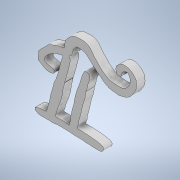
# Autodesk Inventor part: PI
Saved by Autodesk Inventor 2022.6 (Build 266554000, 554)
## iProperties
Created: 2024-11-29
Part Number: PI
Material: Generic
Document SubType Name: Modeling
Designer: Dragos Macovei
Density: 1 g/cm^3
Appearance: Default
Author: Dragos Macovei
Autodesk Inventor part; units mm, degrees
ref_plane "YZ Plane" through (0, 0, 0) normal (1, 0, 0) x (0, 1, 0)
ref_plane "XZ Plane" through (0, 0, 0) normal (0, 1, 0) x (-1, 0, 0)
ref_plane "XY Plane" through (0, 0, 0) normal (0, 0, 1) x (1, 0, 0)
sketch "Sketch1" plane through (0, 0, 0) normal (0, 0, 1) x (1, 0, 0)
  line L0 (0, 0) -> (-40, 0)
  line L1 (-40, 0) -> (-40, 40)
  line L2 (-40, 40) -> (0, 40)
  line L3 (0, 40) -> (0, 0)
  line L4 (-38.5113, 5.4605) -> (-38.1213, 5.6556) construction
  line L5 (-38.1213, 5.6556) -> (-37.6228, 5.8723) construction
  line L6 (-37.6228, 5.8723) -> (-37.2327, 5.8723) construction
  line L7 (-37.2327, 5.8723) -> (-36.6476, 6.089) construction
  line L8 (-36.6476, 6.089) -> (-35.8891, 6.089) construction
  line L9 (-35.8891, 6.089) -> (-34.4588, 6.089) construction
  line L10 (-34.4588, 6.089) -> (-34.4588, 6.6308) construction
  line L11 (-34.4588, 6.6308) -> (-34.1771, 7.3243) construction
  line L12 (-34.1771, 7.3243) -> (-34.0037, 8.1478) construction
  line L13 (-34.0037, 8.1478) -> (-33.7003, 9.058) construction
  line L14 (-33.7003, 9.058) -> (-33.3969, 10.2499) construction
  line L15 (-33.3969, 10.2499) -> (-33.2452, 11.0301) construction
  line L16 (-33.2452, 11.0301) -> (-33.2452, 11.6802) construction
  line L17 (-33.2452, 11.6802) -> (-32.9635, 12.2653) construction
  line L18 (-32.9635, 12.2653) -> (-32.7901, 13.0672) construction
  line L19 (-32.7901, 13.0672) -> (-32.5084, 13.804) construction
  line L20 (-32.5084, 13.804) -> (-32.27, 14.6492) construction
  line L21 (-32.27, 14.6492) -> (-32.075, 15.4293) construction
  line L22 (-32.075, 15.4293) -> (-31.9449, 16.1011) construction
  line L23 (-31.9449, 16.1011) -> (-31.7066, 16.6863) construction
  line L24 (-31.7066, 16.6863) -> (-31.4682, 17.2064) construction
  line L25 (-31.4682, 17.2064) -> (-31.3381, 17.2064) construction
  line L26 (-31.3381, 17.2064) -> (-30.9914, 18.42) construction
  line L27 (-30.9914, 18.42) -> (-30.623, 19.3518) construction
  line L28 (-30.623, 19.3518) -> (-30.2979, 20.2187) construction
  line L29 (-30.2979, 20.2187) -> (-30.1246, 21.3456) construction
  line L30 (-30.1246, 21.3456) -> (-29.7995, 22.3208) construction
  line L31 (-29.7995, 22.3208) -> (-29.6695, 23.2527) construction
  line L32 (-29.6695, 23.2527) -> (-29.4094, 24.0112) construction
  line L33 (-29.4094, 24.0112) -> (-29.171, 24.7913) construction
  line L34 (-29.171, 24.7913) -> (-29.0029, 25.0509) construction
  line L35 (-29.0029, 25.0509) -> (-28.9426, 25.4128) construction
  line L36 (-28.9426, 25.4128) -> (-28.8159, 25.7143) construction
  line L37 (-28.8159, 25.7143) -> (-28.8883, 25.8892) construction
  line L38 (-28.8883, 25.8892) -> (-29.0149, 25.9917) construction
  line L39 (-29.0149, 25.9917) -> (-29.1536, 25.9917) construction
  line L40 (-29.1536, 25.9917) -> (-29.3225, 25.9917) construction
  line L41 (-29.3225, 25.9917) -> (-29.5335, 25.853) construction
  line L42 (-29.5335, 25.853) -> (-29.7265, 25.853) construction
  line L43 (-29.7265, 25.853) -> (-30.0461, 25.8047) construction
  line L44 (-30.0461, 25.8047) -> (-30.6016, 25.6238) construction
  line L45 (-30.6016, 25.6238) -> (-30.9468, 25.541) construction
  line L46 (-30.9468, 25.541) -> (-31.3611, 25.4167) construction
  line L47 (-31.3611, 25.4167) -> (-31.6372, 25.2924) construction
  line L48 (-31.6372, 25.2924) -> (-31.9134, 25.1681) construction
  line L49 (-31.9134, 25.1681) -> (-32.1758, 25.03) construction
  line L50 (-32.1758, 25.03) -> (-32.4105, 24.9058) construction
  line L51 (-32.4105, 24.9058) -> (-32.6314, 24.7677) construction
  line L52 (-32.6314, 24.7677) -> (-32.7833, 24.5882) construction
  line L53 (-32.7833, 24.5882) -> (-33.0595, 24.4363) construction
  line L54 (-33.0595, 24.4363) -> (-33.3218, 24.2844) construction
  line L55 (-33.3218, 24.2844) -> (-33.5566, 24.1463) construction
  line L56 (-33.5566, 24.1463) -> (-33.7913, 23.9806) construction
  line L57 (-33.7913, 23.9806) -> (-34.0122, 23.7597) construction
  line L58 (-34.0122, 23.7597) -> (-34.2332, 23.5526) construction
  line L59 (-34.2332, 23.5526) -> (-34.3713, 23.2488) construction
  line L60 (-34.3713, 23.2488) -> (-34.6336, 23.0279) construction
  line L61 (-34.6336, 23.0279) -> (-34.8407, 22.8069) construction
  line L62 (-34.8407, 22.8069) -> (-34.9512, 22.5308) construction
  line L63 (-34.9512, 22.5308) -> (-35.0893, 22.227) construction
  line L64 (-35.0893, 22.227) -> (-35.2136, 22.0199) construction
  line L65 (-35.2136, 22.0199) -> (-35.2136, 21.7299) construction
  line L66 (-35.2136, 21.7299) -> (-35.2136, 21.3985) construction
  line L67 (-35.2136, 21.3985) -> (-35.0585, 21.11) construction
  line L68 (-35.0585, 21.11) -> (-34.4633, 20.7683) construction
  line L69 (-34.4633, 20.7683) -> (-33.2729, 20.5919) construction
  line L70 (-33.2729, 20.5919) -> (-32.2699, 20.4045) construction
  line L71 (-32.2699, 20.4045) -> (-31.9675, 20.2465) construction
  line L72 (-31.9675, 20.2465) -> (-31.8846, 20) construction
  line L73 (-31.8846, 20) -> (-31.7865, 19.5686) construction
  line L74 (-31.7865, 19.5686) -> (-31.907, 19.1111) construction
  line L75 (-31.907, 19.1111) -> (-32.1094, 18.944) construction
  line L76 (-32.1094, 18.944) -> (-32.4437, 18.8296) construction
  line L77 (-32.4437, 18.8296) -> (-32.8308, 18.7064) construction
  line L78 (-32.8308, 18.7064) -> (-33.1827, 18.6536) construction
  line L79 (-33.1827, 18.6536) -> (-33.6226, 18.6536) construction
  line L80 (-33.6226, 18.6536) -> (-34.0713, 18.6536) construction
  line L81 (-34.0713, 18.6536) -> (-34.5464, 18.7768) construction
  line L82 (-34.5464, 18.7768) -> (-35.1007, 18.9704) construction
  line L83 (-35.1007, 18.9704) -> (-35.5846, 19.2431) construction
  line L84 (-35.5846, 19.2431) -> (-36.0333, 19.4807) construction
  line L85 (-36.0333, 19.4807) -> (-36.4292, 19.8062) construction
  line L86 (-36.4292, 19.8062) -> (-36.658, 19.9294) construction
  line L87 (-36.658, 19.9294) -> (-36.9835, 20.1933) construction
  line L88 (-36.9835, 20.1933) -> (-37.4498, 20.2989) construction
  line L89 (-37.4498, 20.2989) -> (-37.4498, 20.7212) construction
  line L90 (-37.4498, 20.7212) -> (-37.4498, 21.3195) construction
  line L91 (-37.4498, 21.3195) -> (-37.3882, 21.9265) construction
  line L92 (-37.3882, 21.9265) -> (-37.3882, 22.6744) construction
  line L93 (-37.3882, 22.6744) -> (-37.3882, 23.1583) construction
  line L94 (-37.3882, 23.1583) -> (-37.1243, 23.4662) construction
  line L95 (-37.1243, 23.4662) -> (-36.8603, 23.7653) construction
  line L96 (-36.8603, 23.7653) -> (-36.5524, 24.126) construction
  line L97 (-36.5524, 24.126) -> (-36.0685, 24.6451) construction
  line L98 (-36.0685, 24.6451) -> (-35.699, 24.9795) construction
  line L99 (-35.699, 24.9795) -> (-35.1359, 25.4106) construction
  line L100 (-35.1359, 25.4106) -> (-34.8368, 25.7361) construction
  line L101 (-34.8368, 25.7361) -> (-34.5376, 26.1672) construction
  line L102 (-34.5376, 26.1672) -> (-34.1857, 26.5103) construction
  line L103 (-34.1857, 26.5103) -> (-33.7986, 26.8534) construction
  line L104 (-33.7986, 26.8534) -> (-33.3763, 27.0734) construction
  line L105 (-33.3763, 27.0734) -> (-32.778, 27.2846) construction
  line L106 (-32.778, 27.2846) -> (-32.2501, 27.5133) construction
  line L107 (-32.2501, 27.5133) -> (-31.6343, 27.7421) construction
  line L108 (-31.6343, 27.7421) -> (-30.9832, 27.9796) construction
  line L109 (-30.9832, 27.9796) -> (-30.7809, 28.0588) construction
  line L110 (-30.7809, 28.0588) -> (-30.0066, 28.2611) construction
  line L111 (-30.0066, 28.2611) -> (-29.25, 28.3667) construction
  line L112 (-29.25, 28.3667) -> (-28.7749, 28.4547) construction
  line L113 (-28.7749, 28.4547) -> (-28.2294, 28.6395) construction
  line L114 (-28.2294, 28.6395) -> (-28.071, 29.1409) construction
  line L115 (-28.071, 29.1409) -> (-28.1502, 29.9064) construction
  line L116 (-28.1502, 29.9064) -> (-28.0535, 30.4431) construction
  line L117 (-28.0535, 30.4431) -> (-27.8775, 31.1029) construction
  line L118 (-27.8775, 31.1029) -> (-27.5256, 31.5252) construction
  line L119 (-27.5256, 31.5252) -> (-26.7865, 32.5106) construction
  line L120 (-26.7865, 32.5106) -> (-26.2323, 33.0385) construction
  line L121 (-26.2323, 33.0385) -> (-25.4228, 33.54) construction
  line L122 (-25.4228, 33.54) -> (-24.8246, 33.9887) construction
  line L123 (-24.8246, 33.9887) -> (-23.892, 33.9887) construction
  line L124 (-23.892, 33.9887) -> (-22.4227, 34.1295) construction
  line L125 (-22.4227, 34.1295) -> (-21.5253, 34.1295) construction
  line L126 (-21.5253, 34.1295) -> (-20.6455, 34.0063) construction
  line L127 (-20.6455, 34.0063) -> (-19.5633, 33.3904) construction
  line L128 (-19.5633, 33.3904) -> (-18.7539, 32.6514) construction
  line L129 (-18.7539, 32.6514) -> (-18.4899, 32.0795) construction
  line L130 (-18.4899, 32.0795) -> (-17.7597, 31.0061) construction
  line L131 (-17.7597, 31.0061) -> (-16.7479, 30.1351) construction
  line L132 (-16.7479, 30.1351) -> (-16.3696, 29.7568) construction
  line L133 (-16.3696, 29.7568) -> (-15.7889, 28.9474) construction
  line L134 (-15.7889, 28.9474) -> (-14.9707, 28.3491) construction
  line L135 (-14.9707, 28.3491) -> (-13.8798, 27.5309) construction
  line L136 (-13.8798, 27.5309) -> (-12.6392, 26.7831) construction
  line L137 (-12.6392, 26.7831) -> (-11.4163, 26.5895) construction
  line L138 (-11.4163, 26.5895) -> (-8.9352, 26.3696) construction
  line L139 (-8.9352, 26.3696) -> (-7.6067, 26.5631) construction
  line L140 (-7.6067, 26.5631) -> (-6.8325, 27.0646) construction
  line L141 (-6.8325, 27.0646) -> (-6.0671, 27.7772) construction
  line L142 (-6.0671, 27.7772) -> (-5.6724, 28.2872) construction
  line L143 (-5.6724, 28.2872) -> (-5.3394, 28.977) construction
  line L144 (-5.3394, 28.977) -> (-5.1372, 29.7026) construction
  line L145 (-5.1372, 29.7026) -> (-5.1372, 30.2497) construction
  line L146 (-5.1372, 30.2497) -> (-5.2561, 30.9039) construction
  line L147 (-5.2561, 30.9039) -> (-5.4464, 31.4392) construction
  line L148 (-5.4464, 31.4392) -> (-5.7795, 31.8674) construction
  line L149 (-5.7795, 31.8674) -> (-6.1006, 32.129) construction
  line L150 (-6.1006, 32.129) -> (-6.4931, 32.2123) construction
  line L151 (-6.4931, 32.2123) -> (-6.957, 32.1053) construction
  line L152 (-6.957, 32.1053) -> (-7.3376, 31.8436) construction
  line L153 (-7.3376, 31.8436) -> (-7.754, 31.5224) construction
  line L154 (-7.754, 31.5224) -> (-8.0394, 31.3559) construction
  line L155 (-8.0394, 31.3559) -> (-8.0989, 30.9753) construction
  line L156 (-8.0989, 30.9753) -> (-8.0989, 30.4044) construction
  line L157 (-8.0989, 30.4044) -> (-8.2178, 29.9167) construction
  line L158 (-8.2178, 29.9167) -> (-8.5033, 29.774) construction
  line L159 (-8.5033, 29.774) -> (-8.8839, 29.7145) construction
  line L160 (-8.8839, 29.7145) -> (-9.3597, 29.7145) construction
  line L161 (-9.3597, 29.7145) -> (-9.776, 29.7145) construction
  line L162 (-9.776, 29.7145) -> (-10.0377, 30.0951) construction
  line L163 (-10.0377, 30.0951) -> (-10.1923, 30.8207) construction
  line L164 (-10.1923, 30.8207) -> (-10.1923, 31.2608) construction
  line L165 (-10.1923, 31.2608) -> (-10.1923, 31.8317) construction
  line L166 (-10.1923, 31.8317) -> (-10.0139, 32.2718) construction
  spline S0 degree 4 poles (-38.5113, 5.4605) (-38.1213, 5.6556) (-37.6228, 5.8723) (-37.2327, 5.8723) (-36.6476, 6.089) (-35.8891, 6.089) (-34.4588, 6.089) (-34.4588, 6.6308) (-34.1771, 7.3243) (-34.0037, 8.1478) (-33.7003, 9.058) (-33.3969, 10.2499) (-33.2452, 11.0301) (-33.2452, 11.6802) (-32.9635, 12.2653) (-32.7901, 13.0672) (-32.5084, 13.804) (-32.27, 14.6492) (-32.075, 15.4293) (-31.9449, 16.1011) (-31.7066, 16.6863) (-31.4682, 17.2064) (-31.3381, 17.2064) (-30.9914, 18.42) (-30.623, 19.3518) (-30.2979, 20.2187) (-30.1246, 21.3456) (-29.7995, 22.3208) (-29.6695, 23.2527) (-29.4094, 24.0112) (-29.171, 24.7913) (-29.0029, 25.0509) (-28.9426, 25.4128) (-28.8159, 25.7143) (-28.8883, 25.8892) (-29.0149, 25.9917) (-29.1536, 25.9917) (-29.3225, 25.9917) (-29.5335, 25.853) (-29.7265, 25.853) (-30.0461, 25.8047) (-30.6016, 25.6238) (-30.9468, 25.541) (-31.3611, 25.4167) (-31.6372, 25.2924) (-31.9134, 25.1681) (-32.1758, 25.03) (-32.4105, 24.9058) (-32.6314, 24.7677) (-32.7833, 24.5882) (-33.0595, 24.4363) (-33.3218, 24.2844) (-33.5566, 24.1463) (-33.7913, 23.9806) (-34.0122, 23.7597) (-34.2332, 23.5526) (-34.3713, 23.2488) (-34.6336, 23.0279) (-34.8407, 22.8069) (-34.9512, 22.5308) (-35.0893, 22.227) (-35.2136, 22.0199) (-35.2136, 21.7299) (-35.2136, 21.3985) (-35.0585, 21.11) (-34.4633, 20.7683) (-33.2729, 20.5919) (-32.2699, 20.4045) (-31.9675, 20.2465) (-31.8846, 20) (-31.7865, 19.5686) (-31.907, 19.1111) (-32.1094, 18.944) (-32.4437, 18.8296) (-32.8308, 18.7064) (-33.1827, 18.6536) (-33.6226, 18.6536) (-34.0713, 18.6536) (-34.5464, 18.7768) (-35.1007, 18.9704) (-35.5846, 19.2431) (-36.0333, 19.4807) (-36.4292, 19.8062) (-36.658, 19.9294) (-36.9835, 20.1933) (-37.4498, 20.2989) (-37.4498, 20.7212) (-37.4498, 21.3195) (-37.3882, 21.9265) (-37.3882, 22.6744) (-37.3882, 23.1583) (-37.1243, 23.4662) (-36.8603, 23.7653) (-36.5524, 24.126) (-36.0685, 24.6451) (-35.699, 24.9795) (-35.1359, 25.4106) (-34.8368, 25.7361) (-34.5376, 26.1672) (-34.1857, 26.5103) (-33.7986, 26.8534) (-33.3763, 27.0734) (-32.778, 27.2846) (-32.2501, 27.5133) (-31.6343, 27.7421) (-30.9832, 27.9796) (-30.7809, 28.0588) (-30.0066, 28.2611) (-29.25, 28.3667) (-28.7749, 28.4547) (-28.2294, 28.6395) (-28.071, 29.1409) (-28.1502, 29.9064) (-28.0535, 30.4431) (-27.8775, 31.1029) (-27.5256, 31.5252) (-26.7865, 32.5106) (-26.2323, 33.0385) (-25.4228, 33.54) (-24.8246, 33.9887) (-23.892, 33.9887) (-22.4227, 34.1295) (-21.5253, 34.1295) (-20.6455, 34.0063) (-19.5633, 33.3904) (-18.7539, 32.6514) (-18.4899, 32.0795) (-17.7597, 31.0061) (-16.7479, 30.1351) (-16.3696, 29.7568) (-15.7889, 28.9474) (-14.9707, 28.3491) (-13.8798, 27.5309) (-12.6392, 26.7831) (-11.4163, 26.5895) (-8.9352, 26.3696) (-7.6067, 26.5631) (-6.8325, 27.0646) (-6.0671, 27.7772) (-5.6724, 28.2872) (-5.3394, 28.977) (-5.1372, 29.7026) (-5.1372, 30.2497) (-5.2561, 30.9039) (-5.4464, 31.4392) (-5.7795, 31.8674) (-6.1006, 32.129) (-6.4931, 32.2123) (-6.957, 32.1053) (-7.3376, 31.8436) (-7.754, 31.5224) (-8.0394, 31.3559) (-8.0989, 30.9753) (-8.0989, 30.4044) (-8.2178, 29.9167) (-8.5033, 29.774) (-8.8839, 29.7145) (-9.3597, 29.7145) (-9.776, 29.7145) (-10.0377, 30.0951) (-10.1923, 30.8207) (-10.1923, 31.2608) (-10.1923, 31.8317) (-10.0139, 32.2718) knots 1 1 1 1 1 2 3 4 5 6 7 8 9 10 11 12 13 14 15 16 17 18 19 20 21 22 23 24 25 26 27 28 29 30 31 32 33 34 35 36 37 38 39 40 41 42 43 44 45 46 47 48 49 50 51 52 53 54 55 56 57 58 59 60 61 62 63 64 65 66 67 68 69 70 71 72 73 74 75 76 77 78 79 80 81 82 83 84 85 86 87 88 89 90 91 92 93 94 95 96 97 98 99 100 101 102 103 104 105 106 107 108 109 110 111 112 113 114 115 116 117 118 119 120 121 122 123 124 125 126 127 128 129 130 131 132 133 134 135 136 137 138 139 140 141 142 143 144 145 146 147 148 149 150 151 152 153 154 155 156 157 158 159 160 161 161 161 161 161
  line L167 (-10.0139, 32.2718) -> (-9.4005, 32.7746) construction
  line L168 (-9.4005, 32.7746) -> (-8.9956, 33.3904) construction
  line L169 (-8.9956, 33.3904) -> (-8.3606, 33.7391) construction
  line L170 (-8.3606, 33.7391) -> (-7.5143, 33.8958) construction
  line L171 (-7.5143, 33.8958) -> (-6.0119, 33.8958) construction
  line L172 (-6.0119, 33.8958) -> (-4.5966, 33.0834) construction
  line L173 (-4.5966, 33.0834) -> (-4.3603, 32.8921) construction
  line L174 (-4.3603, 32.8921) -> (-3.6113, 32.1588) construction
  line L175 (-3.6113, 32.1588) -> (-3.0306, 31.3559) construction
  line L176 (-3.0306, 31.3559) -> (-3.132, 31.1994) construction
  line L177 (-3.132, 31.1994) -> (-2.9753, 30.1747) construction
  line L178 (-2.9753, 30.1747) -> (-2.9753, 29.1621) construction
  line L179 (-2.9753, 29.1621) -> (-3.2783, 28.1095) construction
  line L180 (-3.2783, 28.1095) -> (-3.9045, 27.1025) construction
  line L181 (-3.9045, 27.1025) -> (-4.4261, 26.3388) construction
  line L182 (-4.4261, 26.3388) -> (-4.8523, 25.7051) construction
  line L183 (-4.8523, 25.7051) -> (-5.6724, 24.9058) construction
  line L184 (-5.6724, 24.9058) -> (-7.0373, 24.1874) construction
  line L185 (-7.0373, 24.1874) -> (-8.437, 23.9806) construction
  line L186 (-8.437, 23.9806) -> (-9.2401, 23.6718) construction
  line L187 (-9.2401, 23.6718) -> (-9.9634, 23.9129) construction
  line L188 (-9.9634, 23.9129) -> (-10.8311, 23.9806) construction
  line L189 (-10.8311, 23.9806) -> (-11.0451, 24.0112) construction
  line L190 (-11.0451, 24.0112) -> (-11.9632, 24.0112) construction
  line L191 (-11.9632, 24.0112) -> (-12.9431, 24.3856) construction
  line L192 (-12.9431, 24.3856) -> (-13.8273, 24.8123) construction
  line L193 (-13.8273, 24.8123) -> (-14.6055, 25.2924) construction
  line L194 (-14.6055, 25.2924) -> (-15.2492, 25.9516) construction
  line L195 (-15.2492, 25.9516) -> (-16.0078, 26.4663) construction
  line L196 (-16.0078, 26.4663) -> (-16.8596, 27.157) construction
  line L197 (-16.8596, 27.157) -> (-17.9191, 28.0322) construction
  line L198 (-17.9191, 28.0322) -> (-18.7539, 28.8281) construction
  line L199 (-18.7539, 28.8281) -> (-19.5633, 29.6247) construction
  line L200 (-19.5633, 29.6247) -> (-20.1913, 30.1747) construction
  line L201 (-20.1913, 30.1747) -> (-20.7799, 30.6727) construction
  line L202 (-20.7799, 30.6727) -> (-21.6339, 30.9753) construction
  line L203 (-21.6339, 30.9753) -> (-22.3926, 31.135) construction
  line L204 (-22.3926, 31.135) -> (-23.7401, 31.201) construction
  line L205 (-23.7401, 31.201) -> (-24.0996, 31.0212) construction
  line L206 (-24.0996, 31.0212) -> (-24.6877, 30.4431) construction
  line L207 (-24.6877, 30.4431) -> (-25.1237, 29.774) construction
  line L208 (-25.1237, 29.774) -> (-25.3575, 28.9099) construction
  line L209 (-25.3575, 28.9099) -> (-25.5979, 27.94) construction
  line L210 (-25.5979, 27.94) -> (-25.7727, 27.6701) construction
  line L211 (-25.7727, 27.6701) -> (-26.12, 27.157) construction
  line L212 (-26.12, 27.157) -> (-26.5862, 27.157) construction
  line L213 (-26.5862, 27.157) -> (-26.5862, 26.8534) construction
  line L214 (-26.5862, 26.8534) -> (-26.3828, 26.5103) construction
  line L215 (-26.3828, 26.5103) -> (-26.0894, 25.9309) construction
  line L216 (-26.0894, 25.9309) -> (-26.3083, 25.1903) construction
  line L217 (-26.3083, 25.1903) -> (-26.7629, 23.2571) construction
  line L218 (-26.7629, 23.2571) -> (-27.156, 21.623) construction
  line L219 (-27.156, 21.623) -> (-27.4261, 20.8331) construction
  line L220 (-27.4261, 20.8331) -> (-27.7015, 19.7665) construction
  line L221 (-27.7015, 19.7665) -> (-28.0535, 18.6536) construction
  line L222 (-28.0535, 18.6536) -> (-28.3111, 18.0193) construction
  spline S1 degree 4 poles (-10.0139, 32.2718) (-9.4005, 32.7746) (-8.9956, 33.3904) (-8.3606, 33.7391) (-7.5143, 33.8958) (-6.0119, 33.8958) (-4.5966, 33.0834) (-4.3603, 32.8921) (-3.6113, 32.1588) (-3.0306, 31.3559) (-3.132, 31.1994) (-2.9753, 30.1747) (-2.9753, 29.1621) (-3.2783, 28.1095) (-3.9045, 27.1025) (-4.4261, 26.3388) (-4.8523, 25.7051) (-5.6724, 24.9058) (-7.0373, 24.1874) (-8.437, 23.9806) (-9.2401, 23.6718) (-9.9634, 23.9129) (-10.8311, 23.9806) (-11.0451, 24.0112) (-11.9632, 24.0112) (-12.9431, 24.3856) (-13.8273, 24.8123) (-14.6055, 25.2924) (-15.2492, 25.9516) (-16.0078, 26.4663) (-16.8596, 27.157) (-17.9191, 28.0322) (-18.7539, 28.8281) (-19.5633, 29.6247) (-20.1913, 30.1747) (-20.7799, 30.6727) (-21.6339, 30.9753) (-22.3926, 31.135) (-23.7401, 31.201) (-24.0996, 31.0212) (-24.6877, 30.4431) (-25.1237, 29.774) (-25.3575, 28.9099) (-25.5979, 27.94) (-25.7727, 27.6701) (-26.12, 27.157) (-26.5862, 27.157) (-26.5862, 26.8534) (-26.3828, 26.5103) (-26.0894, 25.9309) (-26.3083, 25.1903) (-26.7629, 23.2571) (-27.156, 21.623) (-27.4261, 20.8331) (-27.7015, 19.7665) (-28.0535, 18.6536) (-28.3111, 18.0193) knots 1 1 1 1 1 2 3 4 5 6 7 8 9 10 11 12 13 14 15 16 17 18 19 20 21 22 23 24 25 26 27 28 29 30 31 32 33 34 35 36 37 38 39 40 41 42 43 44 45 46 47 48 49 50 51 52 53 54 54 54 54 54
  line L223 (-28.2371, 18.0195) -> (-28.2371, 17.6787) construction
  line L224 (-28.2371, 17.6787) -> (-28.4524, 16.8195) construction
  line L225 (-28.4524, 16.8195) -> (-28.8493, 15.9029) construction
  line L226 (-28.8493, 15.9029) -> (-28.9178, 14.2443) construction
  line L227 (-28.9178, 14.2443) -> (-29.2609, 12.8594) construction
  line L228 (-29.2609, 12.8594) -> (-29.8123, 11.0148) construction
  line L229 (-29.8123, 11.0148) -> (-30.3864, 9.8103) construction
  line L230 (-30.3864, 9.8103) -> (-30.6056, 9.2427) construction
  line L231 (-30.6056, 9.2427) -> (-30.9592, 7.9361) construction
  line L232 (-30.9592, 7.9361) -> (-31.2582, 6.8312) construction
  line L233 (-31.2582, 6.8312) -> (-31.5602, 6.4181) construction
  line L234 (-31.5602, 6.4181) -> (-31.2347, 6.1592) construction
  line L235 (-31.2347, 6.1592) -> (-30.4606, 6.276) construction
  line L236 (-30.4606, 6.276) -> (-28.7781, 6.2021) construction
  line L237 (-28.7781, 6.2021) -> (-26.8855, 6.2021) construction
  line L238 (-26.8855, 6.2021) -> (-26.4616, 5.9825) construction
  line L239 (-26.4616, 5.9825) -> (-26.4616, 6.3942) construction
  spline S2 degree 4 poles (-28.2371, 18.0195) (-28.2371, 17.6787) (-28.4524, 16.8195) (-28.8493, 15.9029) (-28.9178, 14.2443) (-29.2609, 12.8594) (-29.8123, 11.0148) (-30.3864, 9.8103) (-30.6056, 9.2427) (-30.9592, 7.9361) (-31.2582, 6.8312) (-31.5602, 6.4181) (-31.2347, 6.1592) (-30.4606, 6.276) (-28.7781, 6.2021) (-26.8855, 6.2021) (-26.4616, 5.9825) (-26.4616, 6.3942) knots 1 1 1 1 1 2 3 4 5 6 7 8 9 10 11 12 13 14 15 15 15 15 15
  line L240 (-26.4616, 6.3942) -> (-26.4616, 6.8797) construction
  spline S3 degree 1 poles (-26.4616, 6.3942) (-26.4616, 6.8797) knots 1 1 2 2
  line L241 (-26.4616, 6.8797) -> (-26.1248, 7.2287) construction
  line L242 (-26.1248, 7.2287) -> (-26.1248, 7.7425) construction
  line L243 (-26.1248, 7.7425) -> (-26.0575, 8.4229) construction
  line L244 (-26.0575, 8.4229) -> (-26.0575, 9.0832) construction
  line L245 (-26.0575, 9.0832) -> (-25.7964, 9.8353) construction
  line L246 (-25.7964, 9.8353) -> (-25.5888, 11.1919) construction
  line L247 (-25.5888, 11.1919) -> (-25.1918, 12.3025) construction
  line L248 (-25.1918, 12.3025) -> (-24.9357, 12.9856) construction
  line L249 (-24.9357, 12.9856) -> (-24.7988, 14.2693) construction
  line L250 (-24.7988, 14.2693) -> (-24.578, 15.4546) construction
  line L251 (-24.578, 15.4546) -> (-24.2358, 16.7136) construction
  line L252 (-24.2358, 16.7136) -> (-24.2107, 16.7136) construction
  line L253 (-24.2107, 16.7136) -> (-23.8149, 18.1479) construction
  line L254 (-23.8149, 18.1479) -> (-23.2238, 19.6121) construction
  line L255 (-23.2238, 19.6121) -> (-22.7991, 20.6172) construction
  line L256 (-22.7991, 20.6172) -> (-22.4045, 22.2312) construction
  line L257 (-22.4045, 22.2312) -> (-22.066, 23.1717) construction
  line L258 (-22.066, 23.1717) -> (-21.7871, 24.041) construction
  line L259 (-21.7871, 24.041) -> (-21.2651, 24.862) construction
  line L260 (-21.2651, 24.862) -> (-21.0705, 25.2156) construction
  line L261 (-21.0705, 25.2156) -> (-20.5967, 25.2156) construction
  line L262 (-20.5967, 25.2156) -> (-19.7742, 25.1008) construction
  line L263 (-19.7742, 25.1008) -> (-19.4467, 24.7733) construction
  line L264 (-19.4467, 24.7733) -> (-19.2697, 24.399) construction
  line L265 (-19.2697, 24.399) -> (-19.2697, 23.6026) construction
  line L266 (-19.2697, 23.6026) -> (-19.5089, 23.0058) construction
  line L267 (-19.5089, 23.0058) -> (-19.8417, 22.3085) construction
  line L268 (-19.8417, 22.3085) -> (-20.1976, 21.2533) construction
  line L269 (-20.1976, 21.2533) -> (-20.1976, 20.2939) construction
  line L270 (-20.1976, 20.2939) -> (-20.5522, 19.6192) construction
  line L271 (-20.5522, 19.6192) -> (-20.7566, 19.1072) construction
  spline S4 degree 4 poles (-26.4616, 6.8797) (-26.1248, 7.2287) (-26.1248, 7.7425) (-26.0575, 8.4229) (-26.0575, 9.0832) (-25.7964, 9.8353) (-25.5888, 11.1919) (-25.1918, 12.3025) (-24.9357, 12.9856) (-24.7988, 14.2693) (-24.578, 15.4546) (-24.2358, 16.7136) (-24.2107, 16.7136) (-23.8149, 18.1479) (-23.2238, 19.6121) (-22.7991, 20.6172) (-22.4045, 22.2312) (-22.066, 23.1717) (-21.7871, 24.041) (-21.2651, 24.862) (-21.0705, 25.2156) (-20.5967, 25.2156) (-19.7742, 25.1008) (-19.4467, 24.7733) (-19.2697, 24.399) (-19.2697, 23.6026) (-19.5089, 23.0058) (-19.8417, 22.3085) (-20.1976, 21.2533) (-20.1976, 20.2939) (-20.5522, 19.6192) (-20.7566, 19.1072) knots 1 1 1 1 1 2 3 4 5 6 7 8 9 10 11 12 13 14 15 16 17 18 19 20 21 22 23 24 25 26 27 28 29 29 29 29 29
  line L272 (-20.7566, 19.1072) -> (-20.854, 18.5288) construction
  line L273 (-20.854, 18.5288) -> (-20.854, 17.8041) construction
  line L274 (-20.854, 17.8041) -> (-21.117, 16.5872) construction
  line L275 (-21.117, 16.5872) -> (-21.5667, 15.4311) construction
  line L276 (-21.5667, 15.4311) -> (-21.8144, 14.8213) construction
  line L277 (-21.8144, 14.8213) -> (-21.9866, 13.6861) construction
  line L278 (-21.9866, 13.6861) -> (-22.2353, 13.0582) construction
  line L279 (-22.2353, 13.0582) -> (-22.3186, 12.3025) construction
  line L280 (-22.3186, 12.3025) -> (-22.4792, 11.537) construction
  line L281 (-22.4792, 11.537) -> (-22.7415, 10.9107) construction
  line L282 (-22.7415, 10.9107) -> (-22.7991, 10.2651) construction
  line L283 (-22.7991, 10.2651) -> (-23.0731, 9.6541) construction
  line L284 (-23.0731, 9.6541) -> (-23.2575, 8.8628) construction
  line L285 (-23.2575, 8.8628) -> (-23.3202, 8.2445) construction
  line L286 (-23.3202, 8.2445) -> (-23.3202, 7.8753) construction
  line L287 (-23.3202, 7.8753) -> (-23.3031, 7.8753) construction
  line L288 (-23.3031, 7.8753) -> (-23.6141, 7.1963) construction
  line L289 (-23.6141, 7.1963) -> (-23.7272, 6.6837) construction
  line L290 (-23.7272, 6.6837) -> (-23.8458, 6.4199) construction
  line L291 (-23.8458, 6.4199) -> (-23.3363, 6.4199) construction
  line L292 (-23.3363, 6.4199) -> (-19.9643, 6.314) construction
  line L293 (-19.9643, 6.314) -> (-17.6564, 6.0921) construction
  line L294 (-17.6564, 6.0921) -> (-16.0793, 5.8267) construction
  line L295 (-16.0793, 5.8267) -> (-14.9273, 5.5628) construction
  line L296 (-14.9273, 5.5628) -> (-14.4252, 5.0858) construction
  line L297 (-14.4252, 5.0858) -> (-14.6055, 4.2515) construction
  line L298 (-14.6055, 4.2515) -> (-14.9293, 3.8857) construction
  line L299 (-14.9293, 3.8857) -> (-15.3216, 3.4934) construction
  line L300 (-15.3216, 3.4934) -> (-16.7479, 3.4934) construction
  line L301 (-16.7479, 3.4934) -> (-18.3365, 3.4934) construction
  line L302 (-18.3365, 3.4934) -> (-19.3141, 3.5788) construction
  line L303 (-19.3141, 3.5788) -> (-19.6446, 3.713) construction
  line L304 (-19.6446, 3.713) -> (-20.7284, 3.5155) construction
  line L305 (-20.7284, 3.5155) -> (-21.4753, 3.8222) construction
  line L306 (-21.4753, 3.8222) -> (-22.6758, 3.8222) construction
  line L307 (-22.6758, 3.8222) -> (-23.9574, 3.8222) construction
  line L308 (-23.9574, 3.8222) -> (-25.2406, 3.8835) construction
  line L309 (-25.2406, 3.8835) -> (-25.7666, 3.8835) construction
  line L310 (-25.7666, 3.8835) -> (-26.604, 4.0837) construction
  line L311 (-26.604, 4.0837) -> (-27.7265, 4.0041) construction
  line L312 (-27.7265, 4.0041) -> (-28.9447, 4.0931) construction
  line L313 (-28.9447, 4.0931) -> (-30.2052, 4.0931) construction
  line L314 (-30.2052, 4.0931) -> (-31.5315, 3.9952) construction
  line L315 (-31.5315, 3.9952) -> (-31.9422, 3.8021) construction
  line L316 (-31.9422, 3.8021) -> (-33.0068, 3.9133) construction
  line L317 (-33.0068, 3.9133) -> (-34.9512, 3.9745) construction
  line L318 (-34.9512, 3.9745) -> (-36.5524, 3.8613) construction
  line L319 (-36.5524, 3.8613) -> (-37.4109, 4.0217) construction
  line L320 (-37.4109, 4.0217) -> (-37.7112, 4.2648) construction
  line L321 (-37.7112, 4.2648) -> (-38.2609, 4.4494) construction
  line L322 (-38.2609, 4.4494) -> (-38.6136, 4.7356) construction
  line L323 (-38.6136, 4.7356) -> (-38.6136, 5.209) construction
  line L324 (-38.6136, 5.209) -> (-38.5113, 5.4605) construction
  spline S5 degree 4 poles (-20.7566, 19.1072) (-20.854, 18.5288) (-20.854, 17.8041) (-21.117, 16.5872) (-21.5667, 15.4311) (-21.8144, 14.8213) (-21.9866, 13.6861) (-22.2353, 13.0582) (-22.3186, 12.3025) (-22.4792, 11.537) (-22.7415, 10.9107) (-22.7991, 10.2651) (-23.0731, 9.6541) (-23.2575, 8.8628) (-23.3202, 8.2445) (-23.3202, 7.8753) (-23.3031, 7.8753) (-23.6141, 7.1963) (-23.7272, 6.6837) (-23.8458, 6.4199) (-23.3363, 6.4199) (-19.9643, 6.314) (-17.6564, 6.0921) (-16.0793, 5.8267) (-14.9273, 5.5628) (-14.4252, 5.0858) (-14.6055, 4.2515) (-14.9293, 3.8857) (-15.3216, 3.4934) (-16.7479, 3.4934) (-18.3365, 3.4934) (-19.3141, 3.5788) (-19.6446, 3.713) (-20.7284, 3.5155) (-21.4753, 3.8222) (-22.6758, 3.8222) (-23.9574, 3.8222) (-25.2406, 3.8835) (-25.7666, 3.8835) (-26.604, 4.0837) (-27.7265, 4.0041) (-28.9447, 4.0931) (-30.2052, 4.0931) (-31.5315, 3.9952) (-31.9422, 3.8021) (-33.0068, 3.9133) (-34.9512, 3.9745) (-36.5524, 3.8613) (-37.4109, 4.0217) (-37.7112, 4.2648) (-38.2609, 4.4494) (-38.6136, 4.7356) (-38.6136, 5.209) (-38.5113, 5.4605) knots 1 1 1 1 1 2 3 4 5 6 7 8 9 10 11 12 13 14 15 16 17 18 19 20 21 22 23 24 25 26 27 28 29 30 31 32 33 34 35 36 37 38 39 40 41 42 43 44 45 46 47 48 49 50 51 51 51 51 51
  line L325 (-10.0139, 32.2718) -> (-10.0139, 32.2718)
  line L326 (-9.6148, 32.6249) -> (-10.115, 31.9467)
  line L327 (-28.3111, 18.0193) -> (-28.2371, 18.0195)
  dimension "d0" = 40
  dimension "d1" = 40
  constraints: 28 horizontal, 23 vertical, 14 end point, 3 parallel, 1 perpendicular, 16 other
  measures "d0" distance of L1.end L2.end
  measures "d1" distance of L0.end L1.end
extrude "Extrusion1" add sketch "Sketch1" along normal blind 3 contours S0 S1 L327 S2 S3 S4 S5
body "Solid1"
